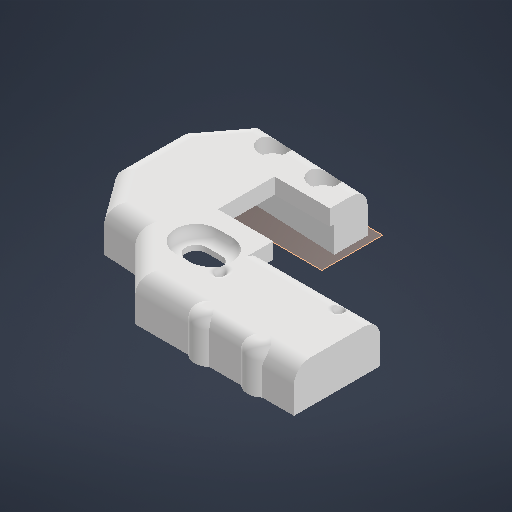
# Autodesk Inventor part: case2
Saved by Autodesk Inventor 2026.2 (Build 302298000, 298)
## iProperties
Created: 2026-10-14
Part Number: case2
Material: Generisch
Document SubType Name: Modeling
Designer: leo
Density: 1 g/cm^3
Appearance: Vorgabe
Author: leo
Autodesk Inventor part; units mm, degrees
ref_plane "YZ Plane" through (0, 0, 0) normal (1, 0, 0) x (0, 1, 0)
ref_plane "XZ Plane" through (0, 0, 0) normal (0, 1, 0) x (-1, 0, 0)
ref_plane "XY Plane" through (0, 0, 0) normal (0, 0, 1) x (1, 0, 0)
ref_plane "Arbeitsebene1" through (-6.8703, 14.8103, -0.0448) normal (0, 0, 1) x (1, 0, 0)
sketch "Skizze1" plane through (-6.8703, 14.8103, -0.0448) normal (0, 0, 1) x (1, 0, 0)
  circle A0 centre (8.0955, 1.5313) radius 2 projected
  circle A1 centre (-1.9045, 1.983) radius 2 projected
  line L0 (-7.4536, 5.2368) -> (-13.7866, -3.0773) projected
  line L1 (-13.7866, -3.0773) -> (-13.7954, -5.2368) projected
  line L2 (-13.7954, -5.2368) -> (-7.6547, -1.0605) projected
  line L3 (-7.6547, -1.0605) -> (13.7954, -2.0296) projected
  line L4 (13.7954, -2.0296) -> (13.7954, 4.2768) projected
  line L5 (13.7954, 4.2768) -> (-7.4536, 5.2368) projected
  line L6 (-8.2359, -17.4588) -> (-13.8298, -13.6548) projected
  line L7 (-13.8298, -13.6548) -> (-13.8386, -15.8023) projected
  line L8 (-13.8386, -15.8023) -> (-8.0006, -23.7723) projected
  line L9 (-8.0006, -23.7723) -> (-1.6886, -24.1723) projected
  line L10 (-1.6886, -24.1723) -> (2.2654, -22.0705) projected
  line L11 (2.2654, -22.0705) -> (2.2654, -20.7162) projected
  line L12 (2.2654, -20.7162) -> (-1.9244, -17.8588) projected
  line L13 (-1.9244, -17.8588) -> (-8.2359, -17.4588) projected
  line L14 (-22.8346, -7.5163) -> (-22.8346, -11.3663) projected
  line L15 (-22.8346, -11.3663) -> (-20.0786, -12.3993) projected
  line L16 (-20.0786, -12.3993) -> (-13.8386, -12.8023) projected
  line L17 (-13.8386, -12.8023) -> (-8.0006, -16.7723) projected
  line L18 (-8.0006, -16.7723) -> (-1.6886, -17.1723) projected
  line L19 (-1.6886, -17.1723) -> (2.9654, -20.3463) projected
  line L20 (2.9654, -20.3463) -> (2.9654, -23.8413) projected
  line L21 (2.9654, -23.8413) -> (6.3654, -27.2413) projected
  line L22 (6.3654, -27.2413) -> (32.9854, -27.2413) projected
  line L23 (32.9854, -27.2413) -> (33.7154, -21.8013) projected
  line L24 (33.7154, -21.8013) -> (33.0154, -15.9413) projected
  line L25 (33.0154, -15.9413) -> (13.7954, -15.9413) projected
  line L26 (13.7954, -15.9413) -> (13.7954, -2.7303) projected
  line L27 (13.7954, -2.7303) -> (-7.4536, -1.7703) projected
  line L28 (-7.4536, -1.7703) -> (-13.7866, -6.0773) projected
  line L29 (-13.7866, -6.0773) -> (-20.0786, -6.4833) projected
  line L30 (-20.0786, -6.4833) -> (-22.8346, -7.5163) projected
  circle A2 centre (2.2554, -16.8813) radius 1.35 projected
  circle A3 centre (5.4294, -4.9633) radius 1 projected
  circle A4 centre (5.4294, -11.4633) radius 1 projected
  circle A5 centre (11.9294, -11.4633) radius 1 projected
  circle A6 centre (8.6794, -8.2133) radius 0.65 projected
  circle A7 centre (11.9294, -4.9633) radius 1 projected
  line L31 (-1.6886, -24.1723) -> (6.3654, -32.2263)
  line L32 (6.3654, -32.2263) -> (36.3654, -32.2263)
  line L33 (36.3654, -32.2263) -> (36.3654, -15.9413)
  line L34 (36.3654, -15.9413) -> (33.6654, -15.9413)
  line L35 (33.6654, -15.9413) -> (34.3654, -21.8013)
  line L36 (34.3654, -21.8013) -> (33.5415, -27.9413)
  line L37 (33.5415, -27.9413) -> (6.3654, -27.9413)
  line L38 (6.3654, -27.9413) -> (2.2654, -23.8413)
  line L39 (2.2654, -23.8413) -> (2.2654, -22.0705)
  circle A8 centre (-1.9045, 1.983) radius 1.5
  circle A9 centre (8.0955, 1.5313) radius 1.5
  circle A10 centre (18.3654, -30.1263) radius 1.6 projected
  circle A11 centre (28.3654, -30.1263) radius 1.6 projected
  circle A12 centre (18.3654, -30.1263) radius 2.9
  circle A13 centre (28.3654, -30.1263) radius 2.9
  point P0 (6.8703, -14.8103)
  point P1 (30.3654, -32.2263)
  point P2 (26.3654, -32.2263)
  point P3 (20.3654, -32.2263)
  point P4 (16.3654, -32.2263)
  dimension "d0" = 30
  dimension "d1" = 90
  dimension "d2" = 2.7
  dimension "d3" = 0.7
  dimension "d6" = 3
  dimension "d7" = 3
  dimension "d34" = 5.8
  dimension "d35" = 5.8
  constraints: 18 end point, 5 parallel, 4 centre point, 4 coincident, 3 horizontal alignment, 2 horizontal, 1 collinear, 1 vertical alignment
  measures "d0" distance of L31.end L32.end
  measures "d1" angle of L33 L32
  measures "d2" distance of L33.end L34.end
  measures "d3" vertical distance of L22.end L36.end
  measures "d6" diameter of A8
  measures "d7" diameter of A9
  measures "d34" diameter of A12
  measures "d35" diameter of A13
extrude "Extrusion1" add sketch "Skizze1" along normal blind 5 contours A0 | A1 | L5 L4 L3 L2 L1 L0 | L13 L12 L11 L10 L9 L8 L7 L6 | L39 L38 L37 A12 L32 L31 L10 | A12 L37 L32 | L32 A12 | A12 L37 A13 L32 | A13 L37 L32 | L32 A13 | A13 L37 L36 L35 L34 L33 L32 | A10 | A11
sketch "Skizze2" plane through (-6.8703, 14.8103, 4.9552) normal (0, 0, 1) x (1, 0, 0)
  line L0 (-13.7866, -3.0773) -> (-13.7954, -5.2368) projected
  line L1 (-13.7954, -5.2368) -> (-7.6547, -1.0605) projected
  line L2 (-7.6547, -1.0605) -> (13.7954, -2.0296) projected
  line L3 (13.7954, -2.0296) -> (13.7954, 4.2768) projected
  line L4 (13.7954, 4.2768) -> (-7.4536, 5.2368) projected
  line L5 (-7.4536, 5.2368) -> (-13.7866, -3.0773) projected
  circle A0 centre (8.0955, 1.5313) radius 1.5 projected
  circle A1 centre (-1.9045, 1.983) radius 1.5 projected
  line L6 (-1.9244, -17.8588) -> (-8.2359, -17.4588) projected
  line L7 (-8.2359, -17.4588) -> (-13.8298, -13.6548) projected
  line L8 (-13.8298, -13.6548) -> (-13.8386, -15.8023) projected
  line L9 (-13.8386, -15.8023) -> (-8.0006, -23.7723) projected
  line L10 (-8.0006, -23.7723) -> (-1.6886, -24.1723) projected
  line L11 (-1.6886, -24.1723) -> (6.3654, -32.2263) projected
  line L12 (6.3654, -32.2263) -> (16.3654, -32.2263) projected
  line L13 (36.3654, -32.2263) -> (36.3654, -15.9413) projected
  line L14 (36.3654, -15.9413) -> (33.6654, -15.9413) projected
  line L15 (33.6654, -15.9413) -> (34.3654, -21.8013) projected
  line L16 (34.3654, -21.8013) -> (33.5415, -27.9413) projected
  line L17 (33.5415, -27.9413) -> (6.3654, -27.9413) projected
  line L18 (6.3654, -27.9413) -> (2.2654, -23.8413) projected
  line L19 (2.2654, -23.8413) -> (2.2654, -20.7162) projected
  line L20 (2.2654, -20.7162) -> (-1.9244, -17.8588) projected
  circle A2 centre (-1.9045, 1.983) radius 2.5
  circle A3 centre (8.0955, 1.5313) radius 2.5
  line L21 (-13.7954, -5.2368) -> (-13.8298, -13.6548)
  line L22 (13.4294, -3.4608) -> (3.9294, -3.4608) projected
  line L23 (3.9294, -3.4608) -> (3.9294, -12.9608) projected
  line L24 (3.9294, -12.9608) -> (13.4294, -12.9608) projected
  line L25 (13.7954, -2.0296) -> (13.7954, -2.8608)
  line L26 (13.7954, -2.0296) -> (14.6266, -2.0296) construction
  line L27 (13.7954, -2.8608) -> (3.3294, -2.8608)
  line L28 (3.3294, -2.8608) -> (3.3294, -13.5608)
  line L29 (3.3294, -13.5608) -> (13.7954, -13.5608)
  line L30 (13.7954, -13.5608) -> (13.7954, -15.9413)
  line L31 (13.7954, -15.9413) -> (33.6654, -15.9413)
  line L32 (11.2754, -21.8413) -> (4.5154, -21.8413) projected
  line L33 (11.2754, -19.8413) -> (11.2754, -21.8413) projected
  line L34 (4.5154, -19.8413) -> (11.2754, -19.8413) projected
  line L35 (4.5154, -21.8413) -> (4.5154, -19.8413) projected
  line L36 (6.4654, -21.5913) -> (6.4654, -20.0913) projected
  line L37 (6.4654, -20.0913) -> (7.9654, -20.0913) projected
  line L38 (7.9654, -20.0913) -> (7.9654, -21.5913) projected
  line L39 (7.9654, -21.5913) -> (6.4654, -21.5913) projected
  line L40 (4.5154, -20.8413) -> (11.2754, -20.8413) construction
  line L41 (6.5154, -22.8413) -> (9.2754, -22.8413)
  line L42 (9.2754, -18.8413) -> (6.5154, -18.8413)
  arc A4 (6.5154, -18.8413) -> (6.5154, -22.8413) centre (6.5154, -20.8413) ccw
  arc A5 (9.2754, -22.8413) -> (9.2754, -18.8413) centre (9.2754, -20.8413) ccw
  line L43 (13.3654, -23.9461) -> (13.3654, -22.9366) projected
  line L44 (13.3654, -24.2413) -> (14.1654, -24.2413) projected
  line L45 (14.1654, -22.6403) -> (13.3654, -22.6403) projected
  line L46 (31.4654, -17.4663) -> (30.6654, -17.4663) projected
  line L47 (30.6654, -19.0673) -> (31.4654, -19.0673) projected
  line L48 (31.4654, -17.7616) -> (31.4654, -18.7711) projected
  line L49 (13.7654, -24.2413) -> (13.7654, -22.6403) construction
  line L50 (14.2654, -23.7413) -> (14.2654, -23.1403)
  line L51 (13.2654, -23.1403) -> (13.2654, -23.7413)
  arc A6 (13.2654, -23.7413) -> (14.2654, -23.7413) centre (13.7654, -23.7413) ccw
  arc A7 (14.2654, -23.1403) -> (13.2654, -23.1403) centre (13.7654, -23.1403) ccw
  line L52 (31.0654, -19.0673) -> (31.0654, -17.4663) construction
  line L53 (31.5654, -18.5673) -> (31.5654, -17.9663)
  line L54 (30.5654, -17.9663) -> (30.5654, -18.5673)
  arc A8 (30.5654, -18.5673) -> (31.5654, -18.5673) centre (31.0654, -18.5673) ccw
  arc A9 (31.5654, -17.9663) -> (30.5654, -17.9663) centre (31.0654, -17.9663) ccw
  arc A10 (16.3654, -32.2263) -> (20.3654, -32.2263) centre (18.3654, -30.1263) ccw projected
  line L55 (20.3654, -32.2263) -> (26.3654, -32.2263) projected
  arc A11 (26.3654, -32.2263) -> (30.3654, -32.2263) centre (28.3654, -30.1263) ccw projected
  line L56 (30.3654, -32.2263) -> (36.3654, -32.2263) projected
  point P0 (6.8703, -14.8103)
  point P1 (7.8954, -20.8413)
  point P2 (13.7654, -23.4408)
  point P3 (31.0654, -18.2668)
  point P4 (4.7834, -21.8413)
  point P5 (4.7834, -19.8413)
  point P6 (11.0075, -19.8413)
  point P7 (11.0075, -21.8413)
  dimension "d8" = 5
  dimension "d9" = 5
  dimension "d10" = 90
  dimension "d11" = 0.6
  dimension "d12" = 0.6
  dimension "d13" = 0.6
  dimension "d14" = 4
  dimension "d15" = 1
  dimension "d16" = 1
  constraints: 40 end point, 18 point on circle, 12 tangent, 9 midpoint, 8 centre point, 7 parallel, 7 point on line, 2 coincident, 2 perpendicular, 1 horizontal, 1 vertical
  measures "d8" diameter of A2
  measures "d9" diameter of A3
  measures "d10" angle of L25 L26
  measures "d11" distance between parallel lines of L27 L22
  measures "d12" distance between parallel lines of L23 L28
  measures "d13" distance between parallel lines of L29 L24
  measures "d14" diameter of A5
  measures "d15" diameter of A7
  measures "d16" diameter of A9
extrude "Extrusion2" add sketch "Skizze2" along normal blind 3 contours L5 L4 L3 L2 L1 L0 | L1 L2 L25 L27 L28 L29 L30 L31 L15 L16 L17 L18 L19 L20 L6 L7 L21 | L7 L6 L20 L19 L18 L17 L16 L15 L14 L13 L56 A11 L55 A10 L12 L11 L10 L9 L8 | L32 A5 L33 | A5 L34 L33 | L32 L35 A4 | L35 L34 A4
sketch "Skizze3" plane through (-6.8703, 14.8103, 4.9552) normal (0, 0, -1) x (-1, 0, 0)
  line L0 (-2.2654, -20.7162) -> (-2.2654, -22.0705) projected
  line L1 (-13.7954, -15.9413) -> (-2.2654, -22.0705) projected
  line L2 (-13.7954, -2.0296) -> (-13.7954, -15.9413) projected
  line L3 (-13.7954, -2.0296) -> (7.6547, -1.0605) projected
  line L4 (7.6547, -1.0605) -> (13.7954, -5.2368) projected
  line L5 (13.8298, -13.6548) -> (13.7954, -5.2368) projected
  line L6 (13.8298, -13.6548) -> (8.2359, -17.4588) projected
  line L7 (8.2359, -17.4588) -> (1.9244, -17.8588) projected
  line L8 (1.9244, -17.8588) -> (-2.2654, -20.7162) projected
  circle A0 centre (-11.9294, -11.4633) radius 1.5 projected
  circle A1 centre (-5.4294, -4.9633) radius 1.5 projected
  circle A2 centre (-5.4294, -11.4633) radius 1.5 projected
  circle A3 centre (-11.9294, -4.9633) radius 1.5 projected
  circle A4 centre (-8.6794, -8.2133) radius 1 projected
  circle A5 centre (-2.2554, -16.8813) radius 2 projected
  line L9 (11.7954, -3.8766) -> (11.7954, -15.0383)
  line L10 (8.2359, -17.4588) -> (13.8298, -13.6548) projected
  line L11 (11.7954, -3.8766) -> (22.9571, -3.8766) construction
  point P0 (-6.8703, -14.8103)
  point P1 (11.7954, -5.245)
  dimension "d19" = 2
  dimension "d20" = 90
  constraints: 4 end point, 2 point on line, 1 horizontal, 1 perpendicular
  measures "d19" distance from line of L5 point (11.795, -5.245)
  measures "d20" angle of L9 L11
extrude "Extrusion3" add sketch "Skizze3" along normal blind 3.5 contours L9 L4 L5 L6
fillet "Rundung1" radius 3 7 edges at (-3.6994, 19.5671, 7.9552) (-17.4904, 15.89, 7.9552) (-20.6829, 5.3705, 7.9552) (-17.7899, -4.977, 7.9552) (-11.7149, -9.162, 7.9552) (-4.5319, -13.389, 7.9552) (4.4951, -17.416, 7.9552)
fillet "Rundung2" radius 2 4 edges at (4.4051, -6.031, 7.9552) (1.0251, -8.031, 7.9552) (-2.3549, -6.031, 7.9552) (1.0251, -4.031, 7.9552) inverted yes
fillet "Rundung3" radius 1 8 edges at (7.3951, -8.6305, 7.9552) (6.8951, -9.431, 7.9552) (6.3951, -8.6305, 7.9552) (6.8951, -7.83, 7.9552) (23.6952, -3.4565, 7.9552) (24.1952, -2.656, 7.9552) (24.6952, -3.4565, 7.9552) (24.1952, -4.257, 7.9552)
sketch "Skizze4" plane through (-6.8703, 14.8103, -0.0448) normal (0, 0, -1) x (-1, 0, 0)
  line L0 (1.9244, -17.8588) -> (8.2359, -17.4588) projected
  line L1 (-2.2654, -20.7162) -> (1.9244, -17.8588) projected
  line L2 (-2.2654, -23.8413) -> (-2.2654, -20.7162) projected
  line L3 (-6.3654, -27.9413) -> (-2.2654, -23.8413) projected
  line L4 (-33.5415, -27.9413) -> (-6.3654, -27.9413) projected
  line L5 (-34.3654, -21.8013) -> (-33.5415, -27.9413) projected
  line L6 (-33.6654, -15.9413) -> (-34.3654, -21.8013) projected
  line L7 (-36.3654, -15.9413) -> (-33.6654, -15.9413) projected
  line L8 (-36.3654, -32.2263) -> (-36.3654, -15.9413) projected
  line L9 (-30.3654, -32.2263) -> (-36.3654, -32.2263) projected
  line L10 (1.6886, -24.1723) -> (-6.3654, -32.2263) projected
  line L11 (8.0006, -23.7723) -> (1.6886, -24.1723) projected
  line L12 (13.8386, -15.8023) -> (8.0006, -23.7723) projected
  line L13 (13.8298, -13.6548) -> (13.8386, -15.8023) projected
  line L14 (8.2359, -17.4588) -> (13.8298, -13.6548) projected
  circle A0 centre (-28.3654, -30.1263) radius 1.5
  circle A1 centre (-18.3654, -30.1263) radius 1.5
  arc A2 (-30.3654, -32.2263) -> (-26.3654, -32.2263) centre (-28.3654, -30.1263) ccw projected
  line L15 (-20.3654, -32.2263) -> (-26.3654, -32.2263) projected
  arc A3 (-20.3654, -32.2263) -> (-16.3654, -32.2263) centre (-18.3654, -30.1263) ccw projected
  line L16 (-6.3654, -32.2263) -> (-16.3654, -32.2263) projected
  point P0 (-6.8703, -14.8103)
  dimension "d26" = 3
  dimension "d27" = 2.1
  dimension "d28" = 8
  dimension "d29" = 3
  dimension "d30" = 10
  constraints: 2 centre point, 1 horizontal alignment
  measures "d26" diameter of A0
  measures "d27" distance from line of A0.centre L9
  measures "d28" distance from line of L8 A0.centre
  measures "d29" diameter of A1
  measures "d30" distance of A1.centre A0.centre
extrude "Extrusion4" cut sketch "Skizze4" against normal blind 5 contours A0 | A1
fillet "Rundung4" radius 3 1 edges at (18.2101, -1.131, 7.9552)
fillet "Rundung5" radius 3 1 edges at (26.4951, -17.416, 7.9552)
fillet "Rundung6" radius 2 4 edges at (24.3071, -16.0254, 7.9552) (21.4951, -18.216, 7.9552) (16.4951, -17.416, 7.9552) (9.9482, -17.7689, 7.9552)
